Autodesk Fusion 360 part; units mm, degrees
(part 2 of 2)
sketch "Sketch5" plane through (0, 0, 8) normal (0, 0, 1) x (-1, 0, 0)
  line L0 (-42.5, -14) -> (-44.5, -14)
  line L1 (-44.5, -14) -> (-44.5, -12)
  line L2 (-44.5, -12) -> (-42.5, -12)
  line L3 (-42.5, -12) -> (-42.5, -14)
  line L4 (-39.9375, -14) -> (-41.9375, -14)
  line L5 (-41.9375, -14) -> (-41.9375, -12)
  line L6 (-41.9375, -12) -> (-39.9375, -12)
  line L7 (-39.9375, -12) -> (-39.9375, -14)
  line L8 (-37.375, -14) -> (-39.375, -14)
  line L9 (-39.375, -14) -> (-39.375, -12)
  line L10 (-39.375, -12) -> (-37.375, -12)
  line L11 (-37.375, -12) -> (-37.375, -14)
  line L12 (-34.8125, -14) -> (-36.8125, -14)
  line L13 (-36.8125, -14) -> (-36.8125, -12)
  line L14 (-36.8125, -12) -> (-34.8125, -12)
  line L15 (-34.8125, -12) -> (-34.8125, -14)
  line L16 (-32.25, -14) -> (-34.25, -14)
  line L17 (-34.25, -14) -> (-34.25, -12)
  line L18 (-34.25, -12) -> (-32.25, -12)
  line L19 (-32.25, -12) -> (-32.25, -14)
  line L20 (-29.6875, -14) -> (-31.6875, -14)
  line L21 (-31.6875, -14) -> (-31.6875, -12)
  line L22 (-31.6875, -12) -> (-29.6875, -12)
  line L23 (-29.6875, -12) -> (-29.6875, -14)
  line L24 (-27.125, -14) -> (-29.125, -14)
  line L25 (-29.125, -14) -> (-29.125, -12)
  line L26 (-29.125, -12) -> (-27.125, -12)
  line L27 (-27.125, -12) -> (-27.125, -14)
  line L28 (-24.5625, -14) -> (-26.5625, -14)
  line L29 (-26.5625, -14) -> (-26.5625, -12)
  line L30 (-26.5625, -12) -> (-24.5625, -12)
  line L31 (-24.5625, -12) -> (-24.5625, -14)
  line L32 (-22, -14) -> (-24, -14)
  line L33 (-24, -14) -> (-24, -12)
  line L34 (-24, -12) -> (-22, -12)
  line L35 (-22, -12) -> (-22, -14)
  line L36 (-19.4375, -14) -> (-21.4375, -14)
  line L37 (-21.4375, -14) -> (-21.4375, -12)
  line L38 (-21.4375, -12) -> (-19.4375, -12)
  line L39 (-19.4375, -12) -> (-19.4375, -14)
  line L40 (-16.875, -14) -> (-18.875, -14)
  line L41 (-18.875, -14) -> (-18.875, -12)
  line L42 (-18.875, -12) -> (-16.875, -12)
  line L43 (-16.875, -12) -> (-16.875, -14)
  line L44 (-14.3125, -14) -> (-16.3125, -14)
  line L45 (-16.3125, -14) -> (-16.3125, -12)
  line L46 (-16.3125, -12) -> (-14.3125, -12)
  line L47 (-14.3125, -12) -> (-14.3125, -14)
  line L48 (-11.75, -14) -> (-13.75, -14)
  line L49 (-13.75, -14) -> (-13.75, -12)
  line L50 (-13.75, -12) -> (-11.75, -12)
  line L51 (-11.75, -12) -> (-11.75, -14)
  line L52 (-9.1875, -14) -> (-11.1875, -14)
  line L53 (-11.1875, -14) -> (-11.1875, -12)
  line L54 (-11.1875, -12) -> (-9.1875, -12)
  line L55 (-9.1875, -12) -> (-9.1875, -14)
  line L56 (-6.625, -14) -> (-8.625, -14)
  line L57 (-8.625, -14) -> (-8.625, -12)
  line L58 (-8.625, -12) -> (-6.625, -12)
  line L59 (-6.625, -12) -> (-6.625, -14)
  line L60 (-4.0625, -14) -> (-6.0625, -14)
  line L61 (-6.0625, -14) -> (-6.0625, -12)
  line L62 (-6.0625, -12) -> (-4.0625, -12)
  line L63 (-4.0625, -12) -> (-4.0625, -14)
  line L64 (-1.5, -14) -> (-3.5, -14)
  line L65 (-3.5, -14) -> (-3.5, -12)
  line L66 (-3.5, -12) -> (-1.5, -12)
  line L67 (-1.5, -12) -> (-1.5, -14)
  line L68 (-42.5, -11.5) -> (-44.5, -11.5)
  line L69 (-44.5, -11.5) -> (-44.5, -9.5)
  line L70 (-44.5, -9.5) -> (-42.5, -9.5)
  line L71 (-42.5, -9.5) -> (-42.5, -11.5)
  line L72 (-39.9375, -11.5) -> (-41.9375, -11.5)
  line L73 (-41.9375, -11.5) -> (-41.9375, -9.5)
  line L74 (-41.9375, -9.5) -> (-39.9375, -9.5)
  line L75 (-39.9375, -9.5) -> (-39.9375, -11.5)
  line L76 (-37.375, -11.5) -> (-39.375, -11.5)
  line L77 (-39.375, -11.5) -> (-39.375, -9.5)
  line L78 (-39.375, -9.5) -> (-37.375, -9.5)
  line L79 (-37.375, -9.5) -> (-37.375, -11.5)
  line L80 (-34.8125, -11.5) -> (-36.8125, -11.5)
  line L81 (-36.8125, -11.5) -> (-36.8125, -9.5)
  line L82 (-36.8125, -9.5) -> (-34.8125, -9.5)
  line L83 (-34.8125, -9.5) -> (-34.8125, -11.5)
  line L84 (-32.25, -11.5) -> (-34.25, -11.5)
  line L85 (-34.25, -11.5) -> (-34.25, -9.5)
  line L86 (-34.25, -9.5) -> (-32.25, -9.5)
  line L87 (-32.25, -9.5) -> (-32.25, -11.5)
  line L88 (-29.6875, -11.5) -> (-31.6875, -11.5)
  line L89 (-31.6875, -11.5) -> (-31.6875, -9.5)
  line L90 (-31.6875, -9.5) -> (-29.6875, -9.5)
  line L91 (-29.6875, -9.5) -> (-29.6875, -11.5)
  line L92 (-27.125, -11.5) -> (-29.125, -11.5)
  line L93 (-29.125, -11.5) -> (-29.125, -9.5)
  line L94 (-29.125, -9.5) -> (-27.125, -9.5)
  line L95 (-27.125, -9.5) -> (-27.125, -11.5)
  line L96 (-24.5625, -11.5) -> (-26.5625, -11.5)
  line L97 (-26.5625, -11.5) -> (-26.5625, -9.5)
  line L98 (-26.5625, -9.5) -> (-24.5625, -9.5)
  line L99 (-24.5625, -9.5) -> (-24.5625, -11.5)
  line L100 (-22, -11.5) -> (-24, -11.5)
  line L101 (-24, -11.5) -> (-24, -9.5)
  line L102 (-24, -9.5) -> (-22, -9.5)
  line L103 (-22, -9.5) -> (-22, -11.5)
  line L104 (-19.4375, -11.5) -> (-21.4375, -11.5)
  line L105 (-21.4375, -11.5) -> (-21.4375, -9.5)
  line L106 (-21.4375, -9.5) -> (-19.4375, -9.5)
  line L107 (-19.4375, -9.5) -> (-19.4375, -11.5)
  line L108 (-16.875, -11.5) -> (-18.875, -11.5)
  line L109 (-18.875, -11.5) -> (-18.875, -9.5)
  line L110 (-18.875, -9.5) -> (-16.875, -9.5)
  line L111 (-16.875, -9.5) -> (-16.875, -11.5)
  line L112 (-14.3125, -11.5) -> (-16.3125, -11.5)
  line L113 (-16.3125, -11.5) -> (-16.3125, -9.5)
  line L114 (-16.3125, -9.5) -> (-14.3125, -9.5)
  line L115 (-14.3125, -9.5) -> (-14.3125, -11.5)
  line L116 (-11.75, -11.5) -> (-13.75, -11.5)
  line L117 (-13.75, -11.5) -> (-13.75, -9.5)
  line L118 (-13.75, -9.5) -> (-11.75, -9.5)
  line L119 (-11.75, -9.5) -> (-11.75, -11.5)
  line L120 (-9.1875, -11.5) -> (-11.1875, -11.5)
  line L121 (-11.1875, -11.5) -> (-11.1875, -9.5)
  line L122 (-11.1875, -9.5) -> (-9.1875, -9.5)
  line L123 (-9.1875, -9.5) -> (-9.1875, -11.5)
  line L124 (-6.625, -11.5) -> (-8.625, -11.5)
  line L125 (-8.625, -11.5) -> (-8.625, -9.5)
  line L126 (-8.625, -9.5) -> (-6.625, -9.5)
  line L127 (-6.625, -9.5) -> (-6.625, -11.5)
  line L128 (-4.0625, -11.5) -> (-6.0625, -11.5)
  line L129 (-6.0625, -11.5) -> (-6.0625, -9.5)
  line L130 (-6.0625, -9.5) -> (-4.0625, -9.5)
  line L131 (-4.0625, -9.5) -> (-4.0625, -11.5)
  line L132 (-1.5, -11.5) -> (-3.5, -11.5)
  line L133 (-3.5, -11.5) -> (-3.5, -9.5)
  line L134 (-3.5, -9.5) -> (-1.5, -9.5)
  line L135 (-1.5, -9.5) -> (-1.5, -11.5)
  line L136 (-42.5, -9) -> (-44.5, -9)
  line L137 (-44.5, -9) -> (-44.5, -7)
  line L138 (-44.5, -7) -> (-42.5, -7)
  line L139 (-42.5, -7) -> (-42.5, -9)
  line L140 (-39.9375, -9) -> (-41.9375, -9)
  line L141 (-41.9375, -9) -> (-41.9375, -7)
  line L142 (-41.9375, -7) -> (-39.9375, -7)
  line L143 (-39.9375, -7) -> (-39.9375, -9)
  line L144 (-37.375, -9) -> (-39.375, -9)
  line L145 (-39.375, -9) -> (-39.375, -7)
  line L146 (-39.375, -7) -> (-37.375, -7)
  line L147 (-37.375, -7) -> (-37.375, -9)
  line L148 (-34.8125, -9) -> (-36.8125, -9)
  line L149 (-36.8125, -9) -> (-36.8125, -7)
  line L150 (-36.8125, -7) -> (-34.8125, -7)
  line L151 (-34.8125, -7) -> (-34.8125, -9)
  line L152 (-32.25, -9) -> (-34.25, -9)
  line L153 (-34.25, -9) -> (-34.25, -7)
  line L154 (-34.25, -7) -> (-32.25, -7)
  line L155 (-32.25, -7) -> (-32.25, -9)
  line L156 (-29.6875, -9) -> (-31.6875, -9)
  line L157 (-31.6875, -9) -> (-31.6875, -7)
  line L158 (-31.6875, -7) -> (-29.6875, -7)
  line L159 (-29.6875, -7) -> (-29.6875, -9)
  line L160 (-27.125, -9) -> (-29.125, -9)
  line L161 (-29.125, -9) -> (-29.125, -7)
  line L162 (-29.125, -7) -> (-27.125, -7)
  line L163 (-27.125, -7) -> (-27.125, -9)
  line L164 (-24.5625, -9) -> (-26.5625, -9)
  line L165 (-26.5625, -9) -> (-26.5625, -7)
  line L166 (-26.5625, -7) -> (-24.5625, -7)
  line L167 (-24.5625, -7) -> (-24.5625, -9)
  line L168 (-22, -9) -> (-24, -9)
  line L169 (-24, -9) -> (-24, -7)
  line L170 (-24, -7) -> (-22, -7)
  line L171 (-22, -7) -> (-22, -9)
  line L172 (-19.4375, -9) -> (-21.4375, -9)
  line L173 (-21.4375, -9) -> (-21.4375, -7)
  line L174 (-21.4375, -7) -> (-19.4375, -7)
  line L175 (-19.4375, -7) -> (-19.4375, -9)
  line L176 (-16.875, -9) -> (-18.875, -9)
  line L177 (-18.875, -9) -> (-18.875, -7)
  line L178 (-18.875, -7) -> (-16.875, -7)
  line L179 (-16.875, -7) -> (-16.875, -9)
  line L180 (-14.3125, -9) -> (-16.3125, -9)
  line L181 (-16.3125, -9) -> (-16.3125, -7)
  line L182 (-16.3125, -7) -> (-14.3125, -7)
  line L183 (-14.3125, -7) -> (-14.3125, -9)
  line L184 (-11.75, -9) -> (-13.75, -9)
  line L185 (-13.75, -9) -> (-13.75, -7)
  line L186 (-13.75, -7) -> (-11.75, -7)
  line L187 (-11.75, -7) -> (-11.75, -9)
  line L188 (-9.1875, -9) -> (-11.1875, -9)
  line L189 (-11.1875, -9) -> (-11.1875, -7)
  line L190 (-11.1875, -7) -> (-9.1875, -7)
  line L191 (-9.1875, -7) -> (-9.1875, -9)
  line L192 (-6.625, -9) -> (-8.625, -9)
  line L193 (-8.625, -9) -> (-8.625, -7)
  line L194 (-8.625, -7) -> (-6.625, -7)
  line L195 (-6.625, -7) -> (-6.625, -9)
  line L196 (-4.0625, -9) -> (-6.0625, -9)
  line L197 (-6.0625, -9) -> (-6.0625, -7)
  line L198 (-6.0625, -7) -> (-4.0625, -7)
  line L199 (-4.0625, -7) -> (-4.0625, -9)
  line L200 (-1.5, -9) -> (-3.5, -9)
  line L201 (-3.5, -9) -> (-3.5, -7)
  line L202 (-3.5, -7) -> (-1.5, -7)
  line L203 (-1.5, -7) -> (-1.5, -9)
  line L204 (-42.5, -6.5) -> (-44.5, -6.5)
  line L205 (-44.5, -6.5) -> (-44.5, -4.5)
  line L206 (-44.5, -4.5) -> (-42.5, -4.5)
  line L207 (-42.5, -4.5) -> (-42.5, -6.5)
  line L208 (-39.9375, -6.5) -> (-41.9375, -6.5)
  line L209 (-41.9375, -6.5) -> (-41.9375, -4.5)
  line L210 (-41.9375, -4.5) -> (-39.9375, -4.5)
  line L211 (-39.9375, -4.5) -> (-39.9375, -6.5)
  line L212 (-37.375, -6.5) -> (-39.375, -6.5)
  line L213 (-39.375, -6.5) -> (-39.375, -4.5)
  line L214 (-39.375, -4.5) -> (-37.375, -4.5)
  line L215 (-37.375, -4.5) -> (-37.375, -6.5)
  line L216 (-34.8125, -6.5) -> (-36.8125, -6.5)
  line L217 (-36.8125, -6.5) -> (-36.8125, -4.5)
  line L218 (-36.8125, -4.5) -> (-34.8125, -4.5)
  line L219 (-34.8125, -4.5) -> (-34.8125, -6.5)
  line L220 (-32.25, -6.5) -> (-34.25, -6.5)
  line L221 (-34.25, -6.5) -> (-34.25, -4.5)
  line L222 (-34.25, -4.5) -> (-32.25, -4.5)
  line L223 (-32.25, -4.5) -> (-32.25, -6.5)
  line L224 (-29.6875, -6.5) -> (-31.6875, -6.5)
  line L225 (-31.6875, -6.5) -> (-31.6875, -4.5)
  line L226 (-31.6875, -4.5) -> (-29.6875, -4.5)
  line L227 (-29.6875, -4.5) -> (-29.6875, -6.5)
  line L228 (-27.125, -6.5) -> (-29.125, -6.5)
  line L229 (-29.125, -6.5) -> (-29.125, -4.5)
  line L230 (-29.125, -4.5) -> (-27.125, -4.5)
  line L231 (-27.125, -4.5) -> (-27.125, -6.5)
  line L232 (-24.5625, -6.5) -> (-26.5625, -6.5)
  line L233 (-26.5625, -6.5) -> (-26.5625, -4.5)
  line L234 (-26.5625, -4.5) -> (-24.5625, -4.5)
  line L235 (-24.5625, -4.5) -> (-24.5625, -6.5)
  line L236 (-22, -6.5) -> (-24, -6.5)
  line L237 (-24, -6.5) -> (-24, -4.5)
  line L238 (-24, -4.5) -> (-22, -4.5)
  line L239 (-22, -4.5) -> (-22, -6.5)
  line L240 (-19.4375, -6.5) -> (-21.4375, -6.5)
  line L241 (-21.4375, -6.5) -> (-21.4375, -4.5)
  line L242 (-21.4375, -4.5) -> (-19.4375, -4.5)
  line L243 (-19.4375, -4.5) -> (-19.4375, -6.5)
  line L244 (-16.875, -6.5) -> (-18.875, -6.5)
  line L245 (-18.875, -6.5) -> (-18.875, -4.5)
  line L246 (-18.875, -4.5) -> (-16.875, -4.5)
  line L247 (-16.875, -4.5) -> (-16.875, -6.5)
  line L248 (-14.3125, -6.5) -> (-16.3125, -6.5)
  line L249 (-16.3125, -6.5) -> (-16.3125, -4.5)
  line L250 (-16.3125, -4.5) -> (-14.3125, -4.5)
  line L251 (-14.3125, -4.5) -> (-14.3125, -6.5)
  line L252 (-11.75, -6.5) -> (-13.75, -6.5)
  line L253 (-13.75, -6.5) -> (-13.75, -4.5)
  line L254 (-13.75, -4.5) -> (-11.75, -4.5)
  line L255 (-11.75, -4.5) -> (-11.75, -6.5)
  line L256 (-9.1875, -6.5) -> (-11.1875, -6.5)
  line L257 (-11.1875, -6.5) -> (-11.1875, -4.5)
  line L258 (-11.1875, -4.5) -> (-9.1875, -4.5)
  line L259 (-9.1875, -4.5) -> (-9.1875, -6.5)
  line L260 (-6.625, -6.5) -> (-8.625, -6.5)
  line L261 (-8.625, -6.5) -> (-8.625, -4.5)
  line L262 (-8.625, -4.5) -> (-6.625, -4.5)
  line L263 (-6.625, -4.5) -> (-6.625, -6.5)
  line L264 (-4.0625, -6.5) -> (-6.0625, -6.5)
  line L265 (-6.0625, -6.5) -> (-6.0625, -4.5)
  line L266 (-6.0625, -4.5) -> (-4.0625, -4.5)
  line L267 (-4.0625, -4.5) -> (-4.0625, -6.5)
  line L268 (-1.5, -6.5) -> (-3.5, -6.5)
  line L269 (-3.5, -6.5) -> (-3.5, -4.5)
  line L270 (-3.5, -4.5) -> (-1.5, -4.5)
  line L271 (-1.5, -4.5) -> (-1.5, -6.5)
  line L272 (-42.5, -4) -> (-44.5, -4)
  line L273 (-44.5, -4) -> (-44.5, -2)
  line L274 (-44.5, -2) -> (-42.5, -2)
  line L275 (-42.5, -2) -> (-42.5, -4)
  line L276 (-39.9375, -4) -> (-41.9375, -4)
  line L277 (-41.9375, -4) -> (-41.9375, -2)
  line L278 (-41.9375, -2) -> (-39.9375, -2)
  line L279 (-39.9375, -2) -> (-39.9375, -4)
  line L280 (-37.375, -4) -> (-39.375, -4)
  line L281 (-39.375, -4) -> (-39.375, -2)
  line L282 (-39.375, -2) -> (-37.375, -2)
  line L283 (-37.375, -2) -> (-37.375, -4)
  line L284 (-34.8125, -4) -> (-36.8125, -4)
  line L285 (-36.8125, -4) -> (-36.8125, -2)
  line L286 (-36.8125, -2) -> (-34.8125, -2)
  line L287 (-34.8125, -2) -> (-34.8125, -4)
  line L288 (-32.25, -4) -> (-34.25, -4)
  line L289 (-34.25, -4) -> (-34.25, -2)
  line L290 (-34.25, -2) -> (-32.25, -2)
  line L291 (-32.25, -2) -> (-32.25, -4)
  line L292 (-29.6875, -4) -> (-31.6875, -4)
  line L293 (-31.6875, -4) -> (-31.6875, -2)
  line L294 (-31.6875, -2) -> (-29.6875, -2)
  line L295 (-29.6875, -2) -> (-29.6875, -4)
  line L296 (-27.125, -4) -> (-29.125, -4)
  line L297 (-29.125, -4) -> (-29.125, -2)
  line L298 (-29.125, -2) -> (-27.125, -2)
  line L299 (-27.125, -2) -> (-27.125, -4)
  line L300 (-24.5625, -4) -> (-26.5625, -4)
  line L301 (-26.5625, -4) -> (-26.5625, -2)
  line L302 (-26.5625, -2) -> (-24.5625, -2)
  line L303 (-24.5625, -2) -> (-24.5625, -4)
  line L304 (-22, -4) -> (-24, -4)
  line L305 (-24, -4) -> (-24, -2)
  line L306 (-24, -2) -> (-22, -2)
  line L307 (-22, -2) -> (-22, -4)
  line L308 (-19.4375, -4) -> (-21.4375, -4)
  line L309 (-21.4375, -4) -> (-21.4375, -2)
  line L310 (-21.4375, -2) -> (-19.4375, -2)
  line L311 (-19.4375, -2) -> (-19.4375, -4)
  line L312 (-16.875, -4) -> (-18.875, -4)
  line L313 (-18.875, -4) -> (-18.875, -2)
  line L314 (-18.875, -2) -> (-16.875, -2)
  line L315 (-16.875, -2) -> (-16.875, -4)
  line L316 (-14.3125, -4) -> (-16.3125, -4)
  line L317 (-16.3125, -4) -> (-16.3125, -2)
  line L318 (-16.3125, -2) -> (-14.3125, -2)
  line L319 (-14.3125, -2) -> (-14.3125, -4)
  line L320 (-11.75, -4) -> (-13.75, -4)
  line L321 (-13.75, -4) -> (-13.75, -2)
  line L322 (-13.75, -2) -> (-11.75, -2)
  line L323 (-11.75, -2) -> (-11.75, -4)
  line L324 (-9.1875, -4) -> (-11.1875, -4)
  line L325 (-11.1875, -4) -> (-11.1875, -2)
  line L326 (-11.1875, -2) -> (-9.1875, -2)
  line L327 (-9.1875, -2) -> (-9.1875, -4)
  line L328 (-6.625, -4) -> (-8.625, -4)
  line L329 (-8.625, -4) -> (-8.625, -2)
  line L330 (-8.625, -2) -> (-6.625, -2)
  line L331 (-6.625, -2) -> (-6.625, -4)
  line L332 (-4.0625, -4) -> (-6.0625, -4)
  line L333 (-6.0625, -4) -> (-6.0625, -2)
  line L334 (-6.0625, -2) -> (-4.0625, -2)
  line L335 (-4.0625, -2) -> (-4.0625, -4)
  line L336 (-1.5, -32) -> (-3.5, -32)
  line L337 (-3.5, -32) -> (-3.5, -30)
  line L338 (-3.5, -30) -> (-1.5, -30)
  line L339 (-1.5, -30) -> (-1.5, -32)
  line L340 (0, 0) -> (-46, 0)
  line L341 (-46, 0) -> (-46, -34)
  line L342 (-46, -34) -> (0, -34)
  line L343 (0, -34) -> (0, 0)
  line L344 (-4.0625, -32) -> (-6.0625, -32)
  line L345 (-6.0625, -32) -> (-6.0625, -30)
  line L346 (-6.0625, -30) -> (-4.0625, -30)
  line L347 (-4.0625, -30) -> (-4.0625, -32)
  line L348 (-6.625, -32) -> (-8.625, -32)
  line L349 (-8.625, -32) -> (-8.625, -30)
  line L350 (-8.625, -30) -> (-6.625, -30)
  line L351 (-6.625, -30) -> (-6.625, -32)
  line L352 (-9.1875, -32) -> (-11.1875, -32)
  line L353 (-11.1875, -32) -> (-11.1875, -30)
  line L354 (-11.1875, -30) -> (-9.1875, -30)
  line L355 (-9.1875, -30) -> (-9.1875, -32)
  line L356 (-11.75, -32) -> (-13.75, -32)
  line L357 (-13.75, -32) -> (-13.75, -30)
  line L358 (-13.75, -30) -> (-11.75, -30)
  line L359 (-11.75, -30) -> (-11.75, -32)
  line L360 (-14.3125, -32) -> (-16.3125, -32)
  line L361 (-16.3125, -32) -> (-16.3125, -30)
  line L362 (-16.3125, -30) -> (-14.3125, -30)
  line L363 (-14.3125, -30) -> (-14.3125, -32)
  line L364 (-16.875, -32) -> (-18.875, -32)
  line L365 (-18.875, -32) -> (-18.875, -30)
  line L366 (-18.875, -30) -> (-16.875, -30)
  line L367 (-16.875, -30) -> (-16.875, -32)
  line L368 (-19.4375, -32) -> (-21.4375, -32)
  line L369 (-21.4375, -32) -> (-21.4375, -30)
  line L370 (-21.4375, -30) -> (-19.4375, -30)
  line L371 (-19.4375, -30) -> (-19.4375, -32)
  line L372 (-22, -32) -> (-24, -32)
  line L373 (-24, -32) -> (-24, -30)
  line L374 (-24, -30) -> (-22, -30)
  line L375 (-22, -30) -> (-22, -32)
  line L376 (-24.5625, -32) -> (-26.5625, -32)
  line L377 (-26.5625, -32) -> (-26.5625, -30)
  line L378 (-26.5625, -30) -> (-24.5625, -30)
  line L379 (-24.5625, -30) -> (-24.5625, -32)
  line L380 (-27.125, -32) -> (-29.125, -32)
  line L381 (-29.125, -32) -> (-29.125, -30)
  line L382 (-29.125, -30) -> (-27.125, -30)
  line L383 (-27.125, -30) -> (-27.125, -32)
  line L384 (-29.6875, -32) -> (-31.6875, -32)
  line L385 (-31.6875, -32) -> (-31.6875, -30)
  line L386 (-31.6875, -30) -> (-29.6875, -30)
  line L387 (-29.6875, -30) -> (-29.6875, -32)
  line L388 (-32.25, -32) -> (-34.25, -32)
  line L389 (-34.25, -32) -> (-34.25, -30)
  line L390 (-34.25, -30) -> (-32.25, -30)
  line L391 (-32.25, -30) -> (-32.25, -32)
  line L392 (-34.8125, -32) -> (-36.8125, -32)
  line L393 (-36.8125, -32) -> (-36.8125, -30)
  line L394 (-36.8125, -30) -> (-34.8125, -30)
  line L395 (-34.8125, -30) -> (-34.8125, -32)
  line L396 (-37.375, -32) -> (-39.375, -32)
  line L397 (-39.375, -32) -> (-39.375, -30)
  line L398 (-39.375, -30) -> (-37.375, -30)
  line L399 (-37.375, -30) -> (-37.375, -32)
  line L400 (-39.9375, -32) -> (-41.9375, -32)
  line L401 (-41.9375, -32) -> (-41.9375, -30)
  line L402 (-41.9375, -30) -> (-39.9375, -30)
  line L403 (-39.9375, -30) -> (-39.9375, -32)
  line L404 (-42.5, -32) -> (-44.5, -32)
  line L405 (-44.5, -32) -> (-44.5, -30)
  line L406 (-44.5, -30) -> (-42.5, -30)
  line L407 (-42.5, -30) -> (-42.5, -32)
  line L408 (-1.5, -29.5) -> (-3.5, -29.5)
  line L409 (-3.5, -29.5) -> (-3.5, -27.5)
  line L410 (-3.5, -27.5) -> (-1.5, -27.5)
  line L411 (-1.5, -27.5) -> (-1.5, -29.5)
  line L412 (-4.0625, -29.5) -> (-6.0625, -29.5)
  line L413 (-6.0625, -29.5) -> (-6.0625, -27.5)
  line L414 (-6.0625, -27.5) -> (-4.0625, -27.5)
  line L415 (-4.0625, -27.5) -> (-4.0625, -29.5)
  line L416 (-6.625, -29.5) -> (-8.625, -29.5)
  line L417 (-8.625, -29.5) -> (-8.625, -27.5)
  line L418 (-8.625, -27.5) -> (-6.625, -27.5)
  line L419 (-6.625, -27.5) -> (-6.625, -29.5)
  line L420 (-9.1875, -29.5) -> (-11.1875, -29.5)
  line L421 (-11.1875, -29.5) -> (-11.1875, -27.5)
  line L422 (-11.1875, -27.5) -> (-9.1875, -27.5)
  line L423 (-9.1875, -27.5) -> (-9.1875, -29.5)
  line L424 (-11.75, -29.5) -> (-13.75, -29.5)
  line L425 (-13.75, -29.5) -> (-13.75, -27.5)
  line L426 (-13.75, -27.5) -> (-11.75, -27.5)
  line L427 (-11.75, -27.5) -> (-11.75, -29.5)
  line L428 (-14.3125, -29.5) -> (-16.3125, -29.5)
  line L429 (-16.3125, -29.5) -> (-16.3125, -27.5)
  line L430 (-16.3125, -27.5) -> (-14.3125, -27.5)
  line L431 (-14.3125, -27.5) -> (-14.3125, -29.5)
  line L432 (-16.875, -29.5) -> (-18.875, -29.5)
  line L433 (-18.875, -29.5) -> (-18.875, -27.5)
  line L434 (-18.875, -27.5) -> (-16.875, -27.5)
  line L435 (-16.875, -27.5) -> (-16.875, -29.5)
  line L436 (-19.4375, -29.5) -> (-21.4375, -29.5)
  line L437 (-21.4375, -29.5) -> (-21.4375, -27.5)
  line L438 (-21.4375, -27.5) -> (-19.4375, -27.5)
  line L439 (-19.4375, -27.5) -> (-19.4375, -29.5)
  line L440 (-22, -29.5) -> (-24, -29.5)
  line L441 (-24, -29.5) -> (-24, -27.5)
  line L442 (-24, -27.5) -> (-22, -27.5)
  line L443 (-22, -27.5) -> (-22, -29.5)
  line L444 (-24.5625, -29.5) -> (-26.5625, -29.5)
  line L445 (-26.5625, -29.5) -> (-26.5625, -27.5)
  line L446 (-26.5625, -27.5) -> (-24.5625, -27.5)
  line L447 (-24.5625, -27.5) -> (-24.5625, -29.5)
  line L448 (-27.125, -29.5) -> (-29.125, -29.5)
  line L449 (-29.125, -29.5) -> (-29.125, -27.5)
  line L450 (-29.125, -27.5) -> (-27.125, -27.5)
  line L451 (-27.125, -27.5) -> (-27.125, -29.5)
  line L452 (-29.6875, -29.5) -> (-31.6875, -29.5)
  line L453 (-31.6875, -29.5) -> (-31.6875, -27.5)
  line L454 (-31.6875, -27.5) -> (-29.6875, -27.5)
  line L455 (-29.6875, -27.5) -> (-29.6875, -29.5)
  line L456 (-32.25, -29.5) -> (-34.25, -29.5)
  line L457 (-34.25, -29.5) -> (-34.25, -27.5)
  line L458 (-34.25, -27.5) -> (-32.25, -27.5)
  line L459 (-32.25, -27.5) -> (-32.25, -29.5)
  line L460 (-34.8125, -29.5) -> (-36.8125, -29.5)
  line L461 (-36.8125, -29.5) -> (-36.8125, -27.5)
  line L462 (-36.8125, -27.5) -> (-34.8125, -27.5)
  line L463 (-34.8125, -27.5) -> (-34.8125, -29.5)
  line L464 (-37.375, -29.5) -> (-39.375, -29.5)
  line L465 (-39.375, -29.5) -> (-39.375, -27.5)
  line L466 (-39.375, -27.5) -> (-37.375, -27.5)
  line L467 (-37.375, -27.5) -> (-37.375, -29.5)
  line L468 (-39.9375, -29.5) -> (-41.9375, -29.5)
  line L469 (-41.9375, -29.5) -> (-41.9375, -27.5)
  line L470 (-41.9375, -27.5) -> (-39.9375, -27.5)
  line L471 (-39.9375, -27.5) -> (-39.9375, -29.5)
  line L472 (-42.5, -29.5) -> (-44.5, -29.5)
  line L473 (-44.5, -29.5) -> (-44.5, -27.5)
  line L474 (-44.5, -27.5) -> (-42.5, -27.5)
  line L475 (-42.5, -27.5) -> (-42.5, -29.5)
  line L476 (-1.5, -27) -> (-3.5, -27)
  line L477 (-3.5, -27) -> (-3.5, -25)
  line L478 (-3.5, -25) -> (-1.5, -25)
  line L479 (-1.5, -25) -> (-1.5, -27)
  line L480 (-4.0625, -27) -> (-6.0625, -27)
  line L481 (-6.0625, -27) -> (-6.0625, -25)
  line L482 (-6.0625, -25) -> (-4.0625, -25)
  line L483 (-4.0625, -25) -> (-4.0625, -27)
  line L484 (-6.625, -27) -> (-8.625, -27)
  line L485 (-8.625, -27) -> (-8.625, -25)
  line L486 (-8.625, -25) -> (-6.625, -25)
  line L487 (-6.625, -25) -> (-6.625, -27)
  line L488 (-9.1875, -27) -> (-11.1875, -27)
  line L489 (-11.1875, -27) -> (-11.1875, -25)
  line L490 (-11.1875, -25) -> (-9.1875, -25)
  line L491 (-9.1875, -25) -> (-9.1875, -27)
  line L492 (-11.75, -27) -> (-13.75, -27)
  line L493 (-13.75, -27) -> (-13.75, -25)
  line L494 (-13.75, -25) -> (-11.75, -25)
  line L495 (-11.75, -25) -> (-11.75, -27)
  line L496 (-14.3125, -27) -> (-16.3125, -27)
  line L497 (-16.3125, -27) -> (-16.3125, -25)
  line L498 (-16.3125, -25) -> (-14.3125, -25)
  line L499 (-14.3125, -25) -> (-14.3125, -27)
  line L500 (-16.875, -27) -> (-18.875, -27)
  line L501 (-18.875, -27) -> (-18.875, -25)
  line L502 (-18.875, -25) -> (-16.875, -25)
  line L503 (-16.875, -25) -> (-16.875, -27)
  line L504 (-19.4375, -27) -> (-21.4375, -27)
  line L505 (-21.4375, -27) -> (-21.4375, -25)
  line L506 (-21.4375, -25) -> (-19.4375, -25)
  line L507 (-19.4375, -25) -> (-19.4375, -27)
  line L508 (-22, -27) -> (-24, -27)
  line L509 (-24, -27) -> (-24, -25)
  line L510 (-24, -25) -> (-22, -25)
  line L511 (-22, -25) -> (-22, -27)
  line L512 (-24.5625, -27) -> (-26.5625, -27)
  line L513 (-26.5625, -27) -> (-26.5625, -25)
  line L514 (-26.5625, -25) -> (-24.5625, -25)
  line L515 (-24.5625, -25) -> (-24.5625, -27)
  line L516 (-27.125, -27) -> (-29.125, -27)
  line L517 (-29.125, -27) -> (-29.125, -25)
  line L518 (-29.125, -25) -> (-27.125, -25)
  line L519 (-27.125, -25) -> (-27.125, -27)
  line L520 (-29.6875, -27) -> (-31.6875, -27)
  line L521 (-31.6875, -27) -> (-31.6875, -25)
  line L522 (-31.6875, -25) -> (-29.6875, -25)
  line L523 (-29.6875, -25) -> (-29.6875, -27)
  line L524 (-32.25, -27) -> (-34.25, -27)
  line L525 (-34.25, -27) -> (-34.25, -25)
  line L526 (-34.25, -25) -> (-32.25, -25)
  line L527 (-32.25, -25) -> (-32.25, -27)
  line L528 (-34.8125, -27) -> (-36.8125, -27)
  line L529 (-36.8125, -27) -> (-36.8125, -25)
  line L530 (-36.8125, -25) -> (-34.8125, -25)
  line L531 (-34.8125, -25) -> (-34.8125, -27)
  line L532 (-37.375, -27) -> (-39.375, -27)
  line L533 (-39.375, -27) -> (-39.375, -25)
  line L534 (-39.375, -25) -> (-37.375, -25)
  line L535 (-37.375, -25) -> (-37.375, -27)
  line L536 (-39.9375, -27) -> (-41.9375, -27)
  line L537 (-41.9375, -27) -> (-41.9375, -25)
  line L538 (-41.9375, -25) -> (-39.9375, -25)
  line L539 (-39.9375, -25) -> (-39.9375, -27)
  line L540 (-42.5, -27) -> (-44.5, -27)
  line L541 (-44.5, -27) -> (-44.5, -25)
  line L542 (-44.5, -25) -> (-42.5, -25)
  line L543 (-42.5, -25) -> (-42.5, -27)
  line L544 (-1.5, -24.5) -> (-3.5, -24.5)
  line L545 (-3.5, -24.5) -> (-3.5, -22.5)
  line L546 (-3.5, -22.5) -> (-1.5, -22.5)
  line L547 (-1.5, -22.5) -> (-1.5, -24.5)
  line L548 (-4.0625, -24.5) -> (-6.0625, -24.5)
  line L549 (-6.0625, -24.5) -> (-6.0625, -22.5)
  line L550 (-6.0625, -22.5) -> (-4.0625, -22.5)
  line L551 (-4.0625, -22.5) -> (-4.0625, -24.5)
  line L552 (-6.625, -24.5) -> (-8.625, -24.5)
  line L553 (-8.625, -24.5) -> (-8.625, -22.5)
  line L554 (-8.625, -22.5) -> (-6.625, -22.5)
  line L555 (-6.625, -22.5) -> (-6.625, -24.5)
  line L556 (-9.1875, -24.5) -> (-11.1875, -24.5)
  line L557 (-11.1875, -24.5) -> (-11.1875, -22.5)
  line L558 (-11.1875, -22.5) -> (-9.1875, -22.5)
  line L559 (-9.1875, -22.5) -> (-9.1875, -24.5)
  line L560 (-11.75, -24.5) -> (-13.75, -24.5)
  line L561 (-13.75, -24.5) -> (-13.75, -22.5)
  line L562 (-13.75, -22.5) -> (-11.75, -22.5)
  line L563 (-11.75, -22.5) -> (-11.75, -24.5)
  line L564 (-14.3125, -24.5) -> (-16.3125, -24.5)
  line L565 (-16.3125, -24.5) -> (-16.3125, -22.5)
  line L566 (-16.3125, -22.5) -> (-14.3125, -22.5)
  line L567 (-14.3125, -22.5) -> (-14.3125, -24.5)
  line L568 (-16.875, -24.5) -> (-18.875, -24.5)
  line L569 (-18.875, -24.5) -> (-18.875, -22.5)
  line L570 (-18.875, -22.5) -> (-16.875, -22.5)
  line L571 (-16.875, -22.5) -> (-16.875, -24.5)
  line L572 (-19.4375, -24.5) -> (-21.4375, -24.5)
  line L573 (-21.4375, -24.5) -> (-21.4375, -22.5)
  line L574 (-21.4375, -22.5) -> (-19.4375, -22.5)
  line L575 (-19.4375, -22.5) -> (-19.4375, -24.5)
  line L576 (-22, -24.5) -> (-24, -24.5)
  line L577 (-24, -24.5) -> (-24, -22.5)
  line L578 (-24, -22.5) -> (-22, -22.5)
  line L579 (-22, -22.5) -> (-22, -24.5)
  line L580 (-24.5625, -24.5) -> (-26.5625, -24.5)
  line L581 (-26.5625, -24.5) -> (-26.5625, -22.5)
  line L582 (-26.5625, -22.5) -> (-24.5625, -22.5)
  line L583 (-24.5625, -22.5) -> (-24.5625, -24.5)
  line L584 (-27.125, -24.5) -> (-29.125, -24.5)
  line L585 (-29.125, -24.5) -> (-29.125, -22.5)
  line L586 (-29.125, -22.5) -> (-27.125, -22.5)
  line L587 (-27.125, -22.5) -> (-27.125, -24.5)
  line L588 (-29.6875, -24.5) -> (-31.6875, -24.5)
  line L589 (-31.6875, -24.5) -> (-31.6875, -22.5)
  line L590 (-31.6875, -22.5) -> (-29.6875, -22.5)
  line L591 (-29.6875, -22.5) -> (-29.6875, -24.5)
  line L592 (-32.25, -24.5) -> (-34.25, -24.5)
  line L593 (-34.25, -24.5) -> (-34.25, -22.5)
  line L594 (-34.25, -22.5) -> (-32.25, -22.5)
  line L595 (-32.25, -22.5) -> (-32.25, -24.5)
  line L596 (-34.8125, -24.5) -> (-36.8125, -24.5)
  line L597 (-36.8125, -24.5) -> (-36.8125, -22.5)
  line L598 (-36.8125, -22.5) -> (-34.8125, -22.5)
  line L599 (-34.8125, -22.5) -> (-34.8125, -24.5)
  line L600 (-37.375, -24.5) -> (-39.375, -24.5)
  line L601 (-39.375, -24.5) -> (-39.375, -22.5)
  line L602 (-39.375, -22.5) -> (-37.375, -22.5)
  line L603 (-37.375, -22.5) -> (-37.375, -24.5)
  line L604 (-39.9375, -24.5) -> (-41.9375, -24.5)
  line L605 (-41.9375, -24.5) -> (-41.9375, -22.5)
  line L606 (-41.9375, -22.5) -> (-39.9375, -22.5)
  line L607 (-39.9375, -22.5) -> (-39.9375, -24.5)
  line L608 (-42.5, -24.5) -> (-44.5, -24.5)
  line L609 (-44.5, -24.5) -> (-44.5, -22.5)
  line L610 (-44.5, -22.5) -> (-42.5, -22.5)
  line L611 (-42.5, -22.5) -> (-42.5, -24.5)
  line L612 (-1.5, -22) -> (-3.5, -22)
  line L613 (-3.5, -22) -> (-3.5, -20)
  line L614 (-3.5, -20) -> (-1.5, -20)
  line L615 (-1.5, -20) -> (-1.5, -22)
  line L616 (-4.0625, -22) -> (-6.0625, -22)
  line L617 (-6.0625, -22) -> (-6.0625, -20)
  line L618 (-6.0625, -20) -> (-4.0625, -20)
  line L619 (-4.0625, -20) -> (-4.0625, -22)
  line L620 (-6.625, -22) -> (-8.625, -22)
  line L621 (-8.625, -22) -> (-8.625, -20)
  line L622 (-8.625, -20) -> (-6.625, -20)
  line L623 (-6.625, -20) -> (-6.625, -22)
  line L624 (-9.1875, -22) -> (-11.1875, -22)
  line L625 (-11.1875, -22) -> (-11.1875, -20)
  line L626 (-11.1875, -20) -> (-9.1875, -20)
  line L627 (-9.1875, -20) -> (-9.1875, -22)
  line L628 (-11.75, -22) -> (-13.75, -22)
  line L629 (-13.75, -22) -> (-13.75, -20)
  line L630 (-13.75, -20) -> (-11.75, -20)
  line L631 (-11.75, -20) -> (-11.75, -22)
  line L632 (-14.3125, -22) -> (-16.3125, -22)
  line L633 (-16.3125, -22) -> (-16.3125, -20)
  line L634 (-16.3125, -20) -> (-14.3125, -20)
  line L635 (-14.3125, -20) -> (-14.3125, -22)
  line L636 (-16.875, -22) -> (-18.875, -22)
  line L637 (-18.875, -22) -> (-18.875, -20)
  line L638 (-18.875, -20) -> (-16.875, -20)
  line L639 (-16.875, -20) -> (-16.875, -22)
  line L640 (-19.4375, -22) -> (-21.4375, -22)
  line L641 (-21.4375, -22) -> (-21.4375, -20)
  line L642 (-21.4375, -20) -> (-19.4375, -20)
  line L643 (-19.4375, -20) -> (-19.4375, -22)
  line L644 (-22, -22) -> (-24, -22)
  line L645 (-24, -22) -> (-24, -20)
  line L646 (-24, -20) -> (-22, -20)
  line L647 (-22, -20) -> (-22, -22)
  line L648 (-24.5625, -22) -> (-26.5625, -22)
  line L649 (-26.5625, -22) -> (-26.5625, -20)
  line L650 (-26.5625, -20) -> (-24.5625, -20)
  line L651 (-24.5625, -20) -> (-24.5625, -22)
  line L652 (-27.125, -22) -> (-29.125, -22)
  line L653 (-29.125, -22) -> (-29.125, -20)
  line L654 (-29.125, -20) -> (-27.125, -20)
  line L655 (-27.125, -20) -> (-27.125, -22)
  line L656 (-29.6875, -22) -> (-31.6875, -22)
  line L657 (-31.6875, -22) -> (-31.6875, -20)
  line L658 (-31.6875, -20) -> (-29.6875, -20)
  line L659 (-29.6875, -20) -> (-29.6875, -22)
  line L660 (-32.25, -22) -> (-34.25, -22)
  line L661 (-34.25, -22) -> (-34.25, -20)
  line L662 (-34.25, -20) -> (-32.25, -20)
  line L663 (-32.25, -20) -> (-32.25, -22)
  line L664 (-34.8125, -22) -> (-36.8125, -22)
  line L665 (-36.8125, -22) -> (-36.8125, -20)
  line L666 (-36.8125, -20) -> (-34.8125, -20)
  line L667 (-34.8125, -20) -> (-34.8125, -22)
  line L668 (-37.375, -22) -> (-39.375, -22)
  line L669 (-39.375, -22) -> (-39.375, -20)
  line L670 (-39.375, -20) -> (-37.375, -20)
  line L671 (-37.375, -20) -> (-37.375, -22)
  line L672 (-39.9375, -22) -> (-41.9375, -22)
  line L673 (-41.9375, -22) -> (-41.9375, -20)
  line L674 (-41.9375, -20) -> (-39.9375, -20)
  line L675 (-39.9375, -20) -> (-39.9375, -22)
  line L676 (-42.5, -22) -> (-44.5, -22)
  line L677 (-44.5, -22) -> (-44.5, -20)
  line L678 (-44.5, -20) -> (-42.5, -20)
  line L679 (-42.5, -20) -> (-42.5, -22)
  line L680 (-7.5, -15) -> (-7.5, -19)
  line L681 (-7.5, -19) -> (-38.5, -19)
  line L682 (-38.5, -19) -> (-38.5, -15)
  line L683 (-38.5, -15) -> (-7.5, -15)
  line L684 (-3.5, -2) -> (-1.5, -2)
  line L685 (-1.5, -2) -> (-1.5, -4)
  line L686 (-1.5, -4) -> (-3.5, -4)
  line L687 (-3.5, -4) -> (-3.5, -2)
  circle A0 centre (-4.5, -17) radius 1.75
  circle A1 centre (-41.5, -17) radius 1.75
  dimension "d41" = 3.5
  dimension "d42" = 3
  dimension "d43" = 3.5
  dimension "d44" = 3
  dimension "d45" = 3
  dimension "d46" = 3
  measures "d41" diameter of A0
  measures "d42" distance of L680 A0.centre
  measures "d43" diameter of A1
  measures "d44" distance of L682 A1.centre
  measures "d45" distance of L618 A0.centre
  measures "d46" distance of L674 A1.centre
extrude "Extrude5" cut sketch "Sketch5" against normal blind 3 contours A0 | A1 bodies 1
sketch "Sketch6" plane through (0, 0, 5) normal (0, 0, 1) x (-1, 0, 0)
  circle A0 centre (-41.5, -17) radius 1.75
  circle A1 centre (-4.5002, -16.9999) radius 0.75
  circle A2 centre (-41.5, -17) radius 0.75
  dimension "d49" = 1.5
  dimension "d50" = 1.5
  constraint concentric A0 A2
  measures "d49" diameter of A1
  measures "d50" diameter of A2
extrude "Extrude6" cut sketch "Sketch6" against normal blind 2 contours A1 | A2 bodies 1
sketch "Sketch7" plane through (46, 0, 0) normal (1, 0, 0) x (0, 1, 0)
  line L0 (0, 8) -> (0, 0)
  line L1 (0, 0) -> (34, 0)
  line L2 (34, 0) -> (34, 8)
  line L3 (34, 8) -> (0, 8)
  line L4 (15, 0) -> (19, 0)
  line L5 (19, 0) -> (19, 5)
  line L6 (19, 5) -> (15, 5)
  line L7 (15, 5) -> (15, 0)
  dimension "d53" = 4
  dimension "d54" = 5
  dimension "d57" = 15
  constraint horizontal L4
  constraint vertical L5
  constraint horizontal L6
  constraint vertical L7
  constraint coincident L1 L4.start
  measures "d53" distance of L4.start L4.end
  measures "d54" distance of L4.start L6.end
  measures "d57" distance of L0 L7
extrude "Extrude7" add sketch "Sketch7" along normal blind 1.5 contours L1 L4 L5 L6 L7 bodies 1
sketch "Sketch8" plane through (0, 0, 5) normal (0, 0, 1) x (-1, 0, 0)
  line L0 (-46, -19) -> (-46, -15)
  line L1 (-46, -15) -> (-47.5, -15)
  line L2 (-47.5, -15) -> (-47.5, -19)
  line L3 (-47.5, -19) -> (-46, -19)
  line L4 (-47.5, -19) -> (-46, -18.8687)
  line L5 (-47.5, -15) -> (-46, -15.1343)
  dimension "d60" = 1.506
  constraint coincident L2.end L3.start
  constraint coincident L0 L4.end
  constraint coincident L1.end L2.start
  constraint coincident L0 L5.end
  measures "d60" distance of L1.end L5.end
extrude "Extrude8" cut sketch "Sketch8" against normal blind 6 contours L0 L3 L4 | L0 L1 L5 bodies 1
sketch "Sketch9" plane through (0, 0, 0) normal (-1, 0, 0) x (0, -1, 0)
  line L0 (0, 0) -> (0, 8)
  line L1 (0, 8) -> (-34, 8)
  line L2 (-34, 8) -> (-34, 0)
  line L3 (-34, 0) -> (0, 0)
  line L4 (-19, 0) -> (-15, 0)
  line L5 (-15, 0) -> (-15, 5)
  line L6 (-15, 5) -> (-19, 5)
  line L7 (-19, 5) -> (-19, 0)
  dimension "d63" = 4
  dimension "d64" = 5
  dimension "d65" = 15
  constraint horizontal L4
  constraint vertical L5
  constraint horizontal L6
  constraint vertical L7
  constraint coincident L3 L4.start
  measures "d63" distance of L4.start L4.end
  measures "d64" distance of L4.start L6.end
  measures "d65" distance of L0 L5
extrude "Extrude9" cut sketch "Sketch9" against normal blind 1.5 contours L3 L4 L5 L6 L7 bodies 1
sketch "Sketch10" plane through (0, 34, 0) normal (0, 1, 0) x (-1, 0, 0)
  line L0 (0, 8) -> (-46, 8)
  line L1 (-46, 8) -> (-46, 0)
  line L2 (-46, 0) -> (0, 0)
  line L3 (0, 0) -> (0, 8)
  line L4 (-25, 0) -> (-21, 0)
  line L5 (-21, 0) -> (-21, 5)
  line L6 (-21, 5) -> (-25, 5)
  line L7 (-25, 5) -> (-25, 0)
  dimension "d68" = 4
  dimension "d69" = 5
  constraint horizontal L4
  constraint vertical L5
  constraint horizontal L6
  constraint vertical L7
  constraint coincident L2 L4.start
  measures "d68" distance of L4.start L4.end
  measures "d69" distance of L4.start L6.end
extrude "Extrude10" add sketch "Sketch10" along normal blind 1.5 contours L2 L4 L5 L6 L7 bodies 1
sketch "Sketch11" plane through (0, 0, 0) normal (0, -1, 0) x (1, 0, 0)
  line L0 (46, 8) -> (0, 8)
  line L1 (0, 8) -> (0, 0)
  line L2 (0, 0) -> (46, 0)
  line L3 (46, 0) -> (46, 8)
  line L4 (21, 0) -> (25, 0)
  line L5 (25, 0) -> (25, 5)
  line L6 (25, 5) -> (21, 5)
  line L7 (21, 5) -> (21, 0)
  dimension "d73" = 4
  dimension "d74" = 5
  dimension "d75" = 21
  constraint horizontal L4
  constraint vertical L5
  constraint horizontal L6
  constraint vertical L7
  constraint coincident L2 L4.start
  measures "d73" distance of L4.start L4.end
  measures "d74" distance of L4.start L6.end
  measures "d75" distance of L3 L5
extrude "Extrude11" cut sketch "Sketch11" against normal blind 1.5 contours L2 L4 L5 L6 L7 bodies 1
sketch "Sketch12" plane through (0, 0, 0) normal (0, 0, -1) x (1, 0, 0)
  line L0 (21, -1.5) -> (21, 0)
  line L1 (21, 0) -> (0, 0)
  line L2 (0, 0) -> (0, -15)
  line L3 (0, -15) -> (1.5, -15)
  line L4 (1.5, -19) -> (0, -19)
  line L5 (0, -19) -> (0, -34)
  line L6 (0, -34) -> (21, -34)
  line L7 (21, -34) -> (21, -35.5)
  line L8 (21, -35.5) -> (25, -35.5)
  line L9 (25, -35.5) -> (25, -34)
  line L10 (25, -34) -> (46, -34)
  line L11 (46, -34) -> (46, -18.8687)
  line L12 (46, -18.8687) -> (47.5, -19)
  line L13 (47.5, -19) -> (47.5, -15)
  line L14 (47.5, -15) -> (46, -15.1343)
  line L15 (46, -15.1343) -> (46, 0)
  line L16 (46, 0) -> (25, 0)
  line L17 (25, 0) -> (25, -1.5)
  line L18 (0, -34) -> (46, -34)
  line L19 (46, -34) -> (46, 0)
  line L20 (46, 0) -> (0, 0)
  line L21 (0, 0) -> (0, -34)
  constraint horizontal L18
  constraint vertical L19
  constraint horizontal L20
  constraint vertical L21
  constraint coincident L15.end L16.start
  constraint coincident L5.end L6.start
extrude "Extrude12" add sketch "Sketch12" along normal blind 1 separate body contours L1 L2 L5 L6 L10 L11 L15 L16 L18 L19 L20 L21 makes body 2
sketch "Sketch13" plane through (0, 0, 5) normal (0, 0, 1) x (-1, 0, 0)
  line L0 (-21, -34) -> (-25, -34)
  line L1 (-25, -34) -> (-25, -35.5)
  line L2 (-25, -35.5) -> (-21, -35.5)
  line L3 (-21, -35.5) -> (-21, -34)
  line L4 (-21, -35.5) -> (-21.1088, -34.004)
  line L5 (-25, -35.5) -> (-24.889, -34.0041)
  line L6 (-24.889, -34.0041) -> (-24.889, -34)
  line L7 (-25, -34) -> (-25, -35.5)
  line L8 (-21.1088, -34.004) -> (-21.1088, -34)
  line L9 (-21, -34) -> (-21, -35.5)
  dimension "d80" = 1.5
  dimension "d81" = 1.5
  constraint coincident L2.end L3.start
  constraint coincident L1.end L2.start
  constraint coincident L0 L6.end
  constraint perpendicular L0 L6
  constraint coincident L0.end L1.start
  constraint coincident L0 L8.end
  constraint perpendicular L0 L8
  constraint coincident L0.start L3.end
  measures "d80" distance of L2.end L4.end
  measures "d81" distance of L1.end L5.end
extrude "Extrude13" cut sketch "Sketch13" against normal blind 7 contours L0 L3 L4 L8 L9 | L0 L1 L5 L6 L7 bodies 1
